rs232-holder (Autodesk Fusion 360 design; units mm, degrees)
part number: 2026-11-12-14-45-31-336
Autodesk Fusion 360 part; units mm, degrees
sketch "profile A (slot 1.2 mm)" plane through (0, 0, 0) normal (0, 0, 1) x (1, 0, 0)
  line L0 (-6.275, 0) -> (6.275, 0)
  line L1 (6.275, 0) -> (6.275, 6.175)
  line L2 (6.275, 6.175) -> (3.975, 6.175)
  line L3 (3.975, 6.175) -> (3.975, 5.175)
  line L4 (3.975, 5.175) -> (4.675, 5.175)
  line L5 (4.675, 5.175) -> (4.675, 3.975)
  line L6 (4.675, 3.975) -> (3.975, 3.975)
  line L7 (3.975, 3.975) -> (3.975, 1.5)
  line L8 (3.975, 1.5) -> (-3.975, 1.5)
  line L9 (-3.975, 1.5) -> (-3.975, 3.975)
  line L10 (-3.975, 3.975) -> (-4.675, 3.975)
  line L11 (-4.675, 3.975) -> (-4.675, 5.175)
  line L12 (-4.675, 5.175) -> (-3.975, 5.175)
  line L13 (-3.975, 5.175) -> (-3.975, 6.175)
  line L14 (-3.975, 6.175) -> (-6.275, 6.175)
  line L15 (-6.275, 6.175) -> (-6.275, 0)
extrude "Extrude1" add sketch "profile A (slot 1.2 mm)" along normal blind 9 makes body 1
chamfer "lead-in A" distance 0.4 angle 45 12 edges at (-4.325, 5.175, 0) (-4.325, 5.175, 9) (-4.675, 4.575, 0) (-4.675, 4.575, 9) (-4.325, 3.975, 0) (-4.325, 3.975, 9) (4.325, 3.975, 0) (4.325, 3.975, 9) (4.675, 4.575, 0) (4.675, 4.575, 9) (4.325, 5.175, 0) (4.325, 5.175, 9) tangent chain off on bodies 1
ref_plane "WorkPlane1" through (0, 0, 1.1) normal (0, 0, 1) x (1, 0, 0)
sketch "mark A1" plane through (0, 0, 1.1) normal (0, 0, 1) x (1, 0, 0)
  line L0 (5.775, 1.5) -> (6.775, 1.5)
  line L1 (6.775, 1.5) -> (6.775, 6.675)
  line L2 (6.775, 6.675) -> (5.775, 6.675)
  line L3 (5.775, 6.675) -> (5.775, 1.5)
extrude "Extrude2" cut sketch "mark A1" along normal blind 0.8 bodies 1
sketch "profile B (slot 1.25 mm)" plane through (0, 0, 0) normal (0, 0, 1) x (1, 0, 0)
  line L0 (11.725, 0) -> (24.275, 0)
  line L1 (24.275, 0) -> (24.275, 6.2)
  line L2 (24.275, 6.2) -> (21.975, 6.2)
  line L3 (21.975, 6.2) -> (21.975, 5.2)
  line L4 (21.975, 5.2) -> (22.675, 5.2)
  line L5 (22.675, 5.2) -> (22.675, 3.95)
  line L6 (22.675, 3.95) -> (21.975, 3.95)
  line L7 (21.975, 3.95) -> (21.975, 1.5)
  line L8 (21.975, 1.5) -> (14.025, 1.5)
  line L9 (14.025, 1.5) -> (14.025, 3.95)
  line L10 (14.025, 3.95) -> (13.325, 3.95)
  line L11 (13.325, 3.95) -> (13.325, 5.2)
  line L12 (13.325, 5.2) -> (14.025, 5.2)
  line L13 (14.025, 5.2) -> (14.025, 6.2)
  line L14 (14.025, 6.2) -> (11.725, 6.2)
  line L15 (11.725, 6.2) -> (11.725, 0)
extrude "Extrude3" add sketch "profile B (slot 1.25 mm)" along normal blind 9 separate body makes body 2
chamfer "lead-in B" distance 0.4 angle 45 12 edges at (13.675, 5.2, 0) (13.675, 5.2, 9) (13.325, 4.575, 0) (13.325, 4.575, 9) (13.675, 3.95, 0) (13.675, 3.95, 9) (22.325, 3.95, 0) (22.325, 3.95, 9) (22.675, 4.575, 0) (22.675, 4.575, 9) (22.325, 5.2, 0) (22.325, 5.2, 9) tangent chain off on bodies 2
ref_plane "WorkPlane2" through (0, 0, 1.1) normal (0, 0, 1) x (1, 0, 0)
sketch "mark B1" plane through (0, 0, 1.1) normal (0, 0, 1) x (1, 0, 0)
  line L0 (23.775, 1.5) -> (24.775, 1.5)
  line L1 (24.775, 1.5) -> (24.775, 6.7)
  line L2 (24.775, 6.7) -> (23.775, 6.7)
  line L3 (23.775, 6.7) -> (23.775, 1.5)
extrude "Extrude4" cut sketch "mark B1" along normal blind 0.8 bodies 2
ref_plane "WorkPlane3" through (0, 0, 2.7) normal (0, 0, 1) x (1, 0, 0)
sketch "mark B2" plane through (0, 0, 2.7) normal (0, 0, 1) x (1, 0, 0)
  line L0 (23.775, 1.5) -> (24.775, 1.5)
  line L1 (24.775, 1.5) -> (24.775, 6.7)
  line L2 (24.775, 6.7) -> (23.775, 6.7)
  line L3 (23.775, 6.7) -> (23.775, 1.5)
extrude "Extrude5" cut sketch "mark B2" along normal blind 0.8 bodies 2
delete_body "RemoveBody1" bodies 1
equation "railLen = 9.0 mm" comment "gripped length along the board"
equation "leadIn = 0.4 mm" comment "groove entrance chamfer"
equation "slotA = 1.2 mm" comment "groove height, variant A"
equation "d4 = railLen"
equation "d6 = leadIn"
equation "slotB = 1.25 mm" comment "groove height, variant B"
equation "d12 = railLen"
equation "d14 = leadIn"
named bodies: "RS232 slot holder A", "RS232 holder (1.25 slot)"
